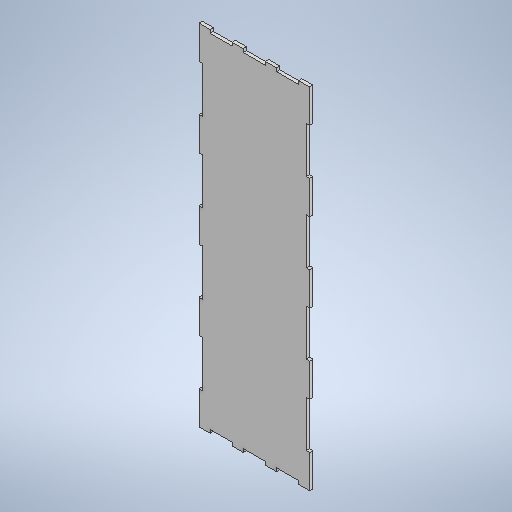
# Autodesk Inventor part: pared1
Saved by Autodesk Inventor 2025.2 (Build 292293000, 293)
## iProperties
Created: 2025-05-19
Part Number: pared1
Material: Generic
Document SubType Name: Modeling
Designer: laura
Density: 1 g/cm^3
Appearance: Default
Author: laura
Autodesk Inventor part; units mm, degrees
ref_plane "YZ Plane" through (0, 0, 0) normal (1, 0, 0) x (0, 1, 0)
ref_plane "XZ Plane" through (0, 0, 0) normal (0, 1, 0) x (-1, 0, 0)
ref_plane "XY Plane" through (0, 0, 0) normal (0, 0, 1) x (1, 0, 0)
sketch "Sketch1" plane through (0, 0, 0) normal (0, 0, 1) x (1, 0, 0)
  line L0 (0, 0) -> (-100, 0)
  line L1 (-100, 0) -> (-100, 316)
  line L2 (-100, 316) -> (0, 316)
  line L3 (0, 316) -> (0, 0)
  dimension "d0" = 316
  dimension "d1" = 100
  constraints: 8 end point, 2 parallel, 1 horizontal, 1 perpendicular
  measures "d0" distance of L2.end L0.start
  measures "d1" distance between parallel lines of L1 L3
extrude "Extrusion1" add sketch "Sketch1" along normal blind 3
sketch "Sketch2" plane through (0, 0, 3) normal (0, 0, 1) x (1, 0, 0)
  line L0 (0, 0) -> (0, 316) projected
  line L1 (0, 286.01) -> (-3, 286.01)
  line L2 (-3, 286.01) -> (-3, 244.4975)
  line L3 (-3, 244.4975) -> (0, 244.4975)
  line L4 (0, 214.5075) -> (-3, 214.5075)
  line L5 (-3, 214.5075) -> (-3, 172.995)
  line L6 (-3, 172.995) -> (0, 172.995)
  line L7 (0, 143.005) -> (-3, 143.005)
  line L8 (-3, 143.005) -> (-3, 101.4925)
  line L9 (-3, 101.4925) -> (0, 101.4925)
  line L10 (0, 71.5025) -> (-3, 71.5025)
  line L11 (-3, 71.5025) -> (-3, 29.99)
  line L12 (-3, 29.99) -> (0, 29.99)
  line L13 (0, 316) -> (-100, 316) projected
  line L14 (-100, 0) -> (0, 0) projected
  line L15 (-9.99, 316) -> (-9.99, 313)
  line L16 (-9.99, 313) -> (-30.0033, 313)
  line L17 (-30.0033, 313) -> (-30.0033, 316)
  line L18 (-39.9933, 316) -> (-39.9933, 313)
  line L19 (-39.9933, 313) -> (-60.0067, 313)
  line L20 (-60.0067, 313) -> (-60.0067, 316)
  line L21 (-69.9967, 316) -> (-69.9967, 313)
  line L22 (-100, 316) -> (-100, 0) projected
  line L23 (-69.9967, 313) -> (-90.01, 313)
  line L24 (-90.01, 313) -> (-90.01, 316)
  line L25 (-50, 0) -> (-50, 316)
  line L26 (-100, 158) -> (0, 158)
  line L27 (-100, 286.01) -> (-97, 286.01)
  line L28 (-97, 286.01) -> (-97, 244.4975)
  line L29 (-97, 244.4975) -> (-100, 244.4975)
  line L30 (-100, 214.5075) -> (-97, 214.5075)
  line L31 (-97, 214.5075) -> (-97, 172.995)
  line L32 (-97, 172.995) -> (-100, 172.995)
  line L33 (-100, 143.005) -> (-97, 143.005)
  line L34 (-97, 143.005) -> (-97, 101.4925)
  line L35 (-97, 101.4925) -> (-100, 101.4925)
  line L36 (-100, 71.5025) -> (-97, 71.5025)
  line L37 (-97, 71.5025) -> (-97, 29.99)
  line L38 (-97, 29.99) -> (-100, 29.99)
  line L39 (-9.99, 0) -> (-9.99, 3)
  line L40 (-9.99, 3) -> (-30.0033, 3)
  line L41 (-30.0033, 3) -> (-30.0033, 0)
  line L42 (-39.9933, 0) -> (-39.9933, 3)
  line L43 (-39.9933, 3) -> (-60.0067, 3)
  line L44 (-60.0067, 3) -> (-60.0067, 0)
  line L45 (-69.9967, 0) -> (-69.9967, 3)
  line L46 (-69.9967, 3) -> (-90.01, 3)
  line L47 (-90.01, 3) -> (-90.01, 0)
  point P0 (-100, 286.01)
  point P1 (-100, 244.4975)
  point P2 (-100, 214.5075)
  point P3 (-100, 172.995)
  point P4 (-100, 143.005)
  point P5 (-100, 101.4925)
  point P6 (-100, 71.5025)
  point P7 (-100, 29.99)
  point P8 (-90.01, 0)
  point P9 (-69.9967, 0)
  point P10 (-60.0067, 0)
  point P11 (-39.9933, 0)
  dimension "d4" = 29.99
  dimension "d5" = 29.99
  dimension "d6" = 29.99
  dimension "d7" = 29.99
  dimension "d8" = 29.99
  dimension "d9" = 3
  dimension "d14" = 9.99
  dimension "d15" = 9.99
  dimension "d16" = 9.99
  dimension "d18" = 9.99
  dimension "d19" = 3
  constraints: 88 end point, 28 symmetric about line, 10 point on line, 8 horizontal, 7 collinear, 5 perpendicular, 4 vertical, 2 midpoint, 2 parallel, 18 other
  measures "d5" distance between parallel lines of L4 L3
  measures "d6" distance between parallel lines of L7 L6
  measures "d7" distance between parallel lines of L10 L9
  measures "d8" distance between parallel lines of L14 L12
  measures "d9" distance of the line from the sketch origin of L8
  measures "d14" distance of the line from the sketch origin of L15
  measures "d15" distance between parallel lines of L18 L17
  measures "d16" distance between parallel lines of L21 L20
  measures "d18" distance between parallel lines of L22 L24
extrude "Extrusion2" cut sketch "Sketch2" against normal through all contours L12 L11 L10 L0 | L9 L8 L7 L0 | L6 L5 L4 L0 | L3 L2 L1 L0
extrude "Extrusion3" cut sketch "Sketch2" against normal through all contours L14 L41 L40 L39 | L14 L25 L43 L42 | L14 L44 L43 L25 | L14 L47 L46 L45 | L25 L13 L18 L19 | L19 L20 L13 L25 | L22 L30 L31 L32 | L33 L34 L35 L22 | L22 L36 L37 L38 | L13 L15 L16 L17 | L21 L23 L24 L13 | L22 L27 L28 L29
equation "\"d1\" = alto"
equation "\"alto\" = 100"
body "Solid1"
